Autodesk Fusion 360 part; units mm, degrees
(part 5 of 6)
equation "lip_t = 3 mm" comment "SOURCE: Control's allocation of 611408 (#279): a 3 mm aluminium lip angle, as the casing"
equation "lip_h = 40 mm" comment "ASSUMPTION: the lip's upright leg on the box's front wall, room for its 3 rivets 20 above the foot leg and below the bulkhead (Z 1698)"
equation "lip_tip = 2 mm" comment "CALCULATION: the lip's tip stays this far off DR's skin (the PM's 25 mm reach less 2)"
equation "lip_end = 5 mm" comment "CALCULATION: the lip's right end this far short of F02 (X 1025.85)"
equation "pad_l = 40 mm" comment "SOURCE: Control's allocation of 618402 (#279): rubber pad 40 x 15 x 5"
equation "pad_w = 15 mm" comment "SOURCE: Control's allocation of 618402 (#279): rubber pad 40 x 15 x 5"
equation "pad_t = 5 mm" comment "SOURCE: Control's allocation of 618402 (#279): rubber pad 40 x 15 x 5"
equation "pad_in = 5 mm" comment "CALCULATION: each pad this far in from the lip's ends: the left at X 678, the right at X 980.85, on F08's free end past the box, since the riser puts the weight centre near the box's right end (about X 940)"
equation "buf_d = 20 mm" comment "ASSUMPTION: the riser buffer's rubber body, about 20 across (product HOLD)"
equation "buf_gap = 0 mm" comment "CALCULATION: the buffer is set to touch F07: about 15 N of the assembly's lean (CEILING, 2026-11-01) holds the riser's foot back with DR's inner panel off"
equation "dr_fac_xa = 1049.7 mm" comment "SOURCE: FRONT's DR STEP on #313 (541fe7f, 350003 P01, every tube 3 off its skin): C04's inner face, front end, X"
equation "dr_fac_ya = -817.11 mm" comment "SOURCE: FRONT's DR STEP on #313 (541fe7f, 350003 P01, every tube 3 off its skin): C04's inner face, front end, Y"
equation "dr_fac_xb = 1217.23 mm" comment "SOURCE: FRONT's DR STEP on #313 (541fe7f, 350003 P01, every tube 3 off its skin): C04's inner face, back end, X"
equation "dr_fac_yb = -666.5 mm" comment "SOURCE: FRONT's DR STEP on #313 (541fe7f, 350003 P01, every tube 3 off its skin): C04's inner face, back end, Y"
equation "ut_clr = 3 mm" comment "ASSUMPTION: the transition keeps this far off C04, so no metal touches DR's frame"
equation "air_sk_ref = 4000 mm" comment "ASSUMPTION: the polygon sketches' reference point sits this far off the origin on both axes, so each corner's dimension stays positive whatever the pod's size (FRONT's sk_ref pattern)"
equation "fac_len = sqrt(( dr_fac_xb - dr_fac_xa ) * ( dr_fac_xb - dr_fac_xa ) + ( dr_fac_yb - dr_fac_ya ) * ( dr_fac_yb - dr_fac_ya ))" comment "CALCULATION: C04's inner face, its length in plan"
equation "ut_ax = dr_fac_xa - ut_clr * ( dr_fac_yb - dr_fac_ya ) / fac_len" comment "CALCULATION: the transition's facet side: C04's inner face moved ut_clr into DR, a point on it, X"
equation "ut_ay = dr_fac_ya + ut_clr * ( dr_fac_xb - dr_fac_xa ) / fac_len" comment "CALCULATION: the same point, Y"
equation "ut_xf = ut_ax + ( -pod_d / 2 + sb_yf - ut_ay ) * ( dr_fac_xb - dr_fac_xa ) / ( dr_fac_yb - dr_fac_ya )" comment "CALCULATION: the transition's facet side meets its front (the box's front line), X (about 1044)"
equation "ut_yr = ut_ay + ( op_x0 + op_w - ut_ax ) * ( dr_fac_yb - dr_fac_ya ) / ( dr_fac_xb - dr_fac_xa )" comment "CALCULATION: the transition's facet side meets its right end (the opening's, X 1161), Y (about -717)"
equation "slv_t = 1 mm" comment "ASSUMPTION: roof sleeve wall, galvanised steel"
equation "rg_t = 2 mm" comment "ASSUMPTION: roof grille plate; 50 % free or more (report 7e), pattern HOLD"
equation "slv_rn_e = 20.0 mm" comment "CALCULATION: rivnut centre to any free edge: 2 x the Ø10.00 hole (D-163; HOLD-04's rule; was 19.2 for the Ø9.53), as the ceiling's"
equation "slv_rn_in = 20 mm" comment "ASSUMPTION: the rivnuts this far in from the slot's corners along their sides"
equation "slv_bulge = 14 mm" comment "ASSUMPTION: a set rivnut's blind-side bulge, about 14 across (the hole FRONT clears for body and bulge, DR model fr_hole_jf; Sherex gives no size)"
equation "slv_rn_clr = 1 mm" comment "ASSUMPTION: the bulge's clearance to cross member 1's back face"
equation "slv_fl_l = 40 mm" comment "CALCULATION: the flange on the slot's left side: its rivnuts slv_rn_e in, slv_rn_e to its edge, rounded up"
equation "slv_fl_f = 15 mm" comment "ASSUMPTION: the flange on the front and right sides: no rivnuts there"
equation "slv_rn_yb = ( pod_d / 2 - wall_depth ) + cs_front - x1_ov + tube_w + slv_bulge / 2 + slv_rn_clr" comment "CALCULATION: the back side's rivnuts behind cross member 1: its back face plus half the bulge plus the clearance (Y -273)"
equation "slv_fl_b = slv_rn_yb + slv_rn_e - ( slot_y0 + slot_d )" comment "CALCULATION: the flange on the slot's back side, out to slv_rn_e behind those rivnuts (about 72)"
equation "d9771 = floor_top"
equation "d9773 = ( ( pod_w / 2 - stack_t - col_gap ) ) - ( col_x0 )"
equation "d9774 = ( ( ( pod_d / 2 - wall_depth ) + col_d ) ) - ( dr_acc_face_y )"
equation "d9775 = abs(col_x0)"
equation "d9776 = abs(dr_acc_face_y)"
equation "d9777 = ( ( floor_top + foot_t ) ) - ( floor_top )"
equation "d9779 = ( floor_top + foot_t ) + grille_z + grille_h"
equation "d9781 = ( ( pod_w / 2 - stack_t - col_gap ) ) - ( col_x0 )"
equation "d9782 = ( ( ( pod_d / 2 - wall_depth ) + col_d ) ) - ( ( ( pod_d / 2 - wall_depth ) + col_d ) - face_t )"
equation "d9783 = abs(col_x0)"
equation "d9784 = abs(( ( pod_d / 2 - wall_depth ) + col_d ) - face_t)"
equation "d9785 = ( dt_zb ) - ( ( floor_top + foot_t ) + grille_z + grille_h )"
equation "d9787 = hub_z - hub_w / 2"
equation "d9789 = ( ( col_x0 + face_t + ang_f + ( pod_w / 2 - stack_t - col_gap ) - ang_f ) / 2 + hub_w / 2 ) - ( ( col_x0 + face_t + ang_f + ( pod_w / 2 - stack_t - col_gap ) - ang_f ) / 2 - hub_w / 2 )"
equation "d9790 = ( ( ( pod_d / 2 - wall_depth ) + col_d ) ) - ( ( ( pod_d / 2 - wall_depth ) + col_d ) - face_t - 40 mm )"
equation "d9791 = abs(( col_x0 + face_t + ang_f + ( pod_w / 2 - stack_t - col_gap ) - ang_f ) / 2 - hub_w / 2)"
equation "d9792 = abs(( ( pod_d / 2 - wall_depth ) + col_d ) - face_t - 40 mm)"
equation "d9793 = ( hub_z + hub_w / 2 ) - ( hub_z - hub_w / 2 )"
equation "d9795 = ( floor_top + foot_t ) + grille_z + grille_h"
equation "d9797 = ( col_x0 + face_t ) - ( col_x0 )"
equation "d9798 = ( ( ( pod_d / 2 - wall_depth ) + col_d ) - face_t ) - ( dr_acc_face_y )"
equation "d9799 = abs(col_x0)"
equation "d9800 = abs(dr_acc_face_y)"
equation "d9801 = ( dt_zb ) - ( ( floor_top + foot_t ) + grille_z + grille_h )"
equation "d9803 = ( floor_top + foot_t )"
equation "d9805 = ( ( pod_w / 2 - stack_t - col_gap ) ) - ( ( pod_w / 2 - stack_t - col_gap ) - plate_t )"
equation "d9806 = ( ( ( pod_d / 2 - wall_depth ) + col_d ) - face_t - ang_w ) - ( dr_acc_face_y )"
equation "d9807 = abs(( pod_w / 2 - stack_t - col_gap ) - plate_t)"
equation "d9808 = abs(dr_acc_face_y)"
equation "d9809 = ( b01_z + fr_wsh_d / 2 + cart_b01_clr ) - ( ( floor_top + foot_t ) )"
equation "d9811 = b01_z + fr_wsh_d / 2 + cart_b01_clr + cart_l"
equation "d9813 = ( ( pod_w / 2 - stack_t - col_gap ) ) - ( ( pod_w / 2 - stack_t - col_gap ) - plate_t )"
equation "d9814 = ( ( ( pod_d / 2 - wall_depth ) + col_d ) - face_t - ang_w ) - ( dr_acc_face_y )"
equation "d9815 = abs(( pod_w / 2 - stack_t - col_gap ) - plate_t)"
equation "d9816 = abs(dr_acc_face_y)"
equation "d9817 = ( dt_zb ) - ( b01_z + fr_wsh_d / 2 + cart_b01_clr + cart_l )"
equation "d9819 = b01_z + fr_wsh_d / 2 + cart_b01_clr"
equation "d9821 = ( ( pod_w / 2 - stack_t - col_gap ) - ang_f ) - ( col_x0 + face_t + ang_f )"
equation "d9822 = ( ( ( pod_d / 2 - wall_depth ) + col_d ) - face_t ) - ( dr_acc_face_y + clr + cart_d )"
equation "d9823 = abs(col_x0 + face_t + ang_f)"
equation "d9824 = abs(dr_acc_face_y + clr + cart_d)"
equation "d9825 = ( b01_z + fr_wsh_d / 2 + cart_b01_clr + cart_l ) - ( b01_z + fr_wsh_d / 2 + cart_b01_clr )"
equation "d9827 = hub_z - hub_w / 2"
equation "d9829 = ( ( col_x0 + face_t + ang_f + ( pod_w / 2 - stack_t - col_gap ) - ang_f ) / 2 + hub_w / 2 ) - ( ( col_x0 + face_t + ang_f + ( pod_w / 2 - stack_t - col_gap ) - ang_f ) / 2 - hub_w / 2 )"
equation "d9830 = ( ( ( pod_d / 2 - wall_depth ) + col_d ) ) - ( ( ( pod_d / 2 - wall_depth ) + col_d ) - face_t - 40 mm )"
equation "d9831 = abs(( col_x0 + face_t + ang_f + ( pod_w / 2 - stack_t - col_gap ) - ang_f ) / 2 - hub_w / 2)"
equation "d9832 = abs(( ( pod_d / 2 - wall_depth ) + col_d ) - face_t - 40 mm)"
equation "d9833 = ( hub_z + hub_w / 2 ) - ( hub_z - hub_w / 2 )"
equation "d9835 = b01_z + fr_wsh_d / 2 + cart_b01_clr"
equation "d9837 = ( ( pod_w / 2 - stack_t - col_gap ) - cart_w ) - ( col_x0 + face_t )"
equation "d9838 = ( dr_acc_face_y + clr + cart_d ) - ( dr_acc_face_y + ang_w )"
equation "d9839 = abs(col_x0 + face_t)"
equation "d9840 = abs(dr_acc_face_y + ang_w)"
equation "d9841 = ( b01_z + fr_wsh_d / 2 + cart_b01_clr + cart_l ) - ( b01_z + fr_wsh_d / 2 + cart_b01_clr )"
equation "d9843 = ( floor_top + foot_t ) + grille_z"
equation "d9845 = ( ( pod_w / 2 - stack_t - col_gap ) ) - ( col_x0 )"
equation "d9846 = ( ( ( pod_d / 2 - wall_depth ) + col_d ) ) - ( ( ( pod_d / 2 - wall_depth ) + col_d ) - grille_t )"
equation "d9847 = abs(col_x0)"
equation "d9848 = abs(( ( pod_d / 2 - wall_depth ) + col_d ) - grille_t)"
equation "d9849 = ( ( floor_top + foot_t ) + grille_z + grille_h ) - ( ( floor_top + foot_t ) + grille_z )"
equation "d9851 = ( floor_top + foot_t ) + grille_z"
equation "d9853 = ( col_x0 + grille_t ) - ( col_x0 )"
equation "d9854 = ( ( ( pod_d / 2 - wall_depth ) + col_d ) - grille_t ) - ( ( ( pod_d / 2 - wall_depth ) + col_d ) - grille_t - grille_l )"
equation "d9855 = abs(col_x0)"
equation "d9856 = abs(( ( pod_d / 2 - wall_depth ) + col_d ) - grille_t - grille_l)"
equation "d9857 = ( ( floor_top + foot_t ) + grille_z + grille_h ) - ( ( floor_top + foot_t ) + grille_z )"
equation "d9859 = hub_z - hub_w / 2"
equation "d9861 = ( ( col_x0 + face_t + ang_f + ( pod_w / 2 - stack_t - col_gap ) - ang_f ) / 2 + hub_w / 2 ) - ( ( col_x0 + face_t + ang_f + ( pod_w / 2 - stack_t - col_gap ) - ang_f ) / 2 - hub_w / 2 )"
equation "d9862 = ( ( ( pod_d / 2 - wall_depth ) + col_d ) ) - ( ( ( pod_d / 2 - wall_depth ) + col_d ) - hub_t )"
equation "d9863 = abs(( col_x0 + face_t + ang_f + ( pod_w / 2 - stack_t - col_gap ) - ang_f ) / 2 - hub_w / 2)"
equation "d9864 = abs(( ( pod_d / 2 - wall_depth ) + col_d ) - hub_t)"
equation "d9865 = ( hub_z + hub_w / 2 ) - ( hub_z - hub_w / 2 )"
equation "d9867 = abs(( col_x0 + face_t ) - ( col_x0 + face_t ))"
equation "d9868 = abs(( ( ( pod_d / 2 - wall_depth ) + col_d ) - face_t - ang_w + ang_w ) - ( ( ( pod_d / 2 - wall_depth ) + col_d ) - face_t - ang_w ))"
equation "d9869 = abs(( col_x0 + face_t + ang_f ) - ( col_x0 + face_t ))"
equation "d9870 = abs(( ( ( pod_d / 2 - wall_depth ) + col_d ) - face_t - ang_w + ang_w - ang_t ) - ( ( ( pod_d / 2 - wall_depth ) + col_d ) - face_t - ang_w ))"
equation "d9871 = abs(( col_x0 + face_t + ang_t ) - ( col_x0 + face_t ))"
equation "d9872 = abs(( ( ( pod_d / 2 - wall_depth ) + col_d ) - face_t - ang_w ) - ( ( ( pod_d / 2 - wall_depth ) + col_d ) - face_t - ang_w ))"
equation "d9873 = ( ( dt_zb ) - ( ( floor_top + foot_t ) ) ) - ( 0 mm )"
equation "d9875 = ( floor_top + foot_t )"
equation "d9877 = abs(col_x0 + face_t)"
equation "d9878 = abs(( ( pod_d / 2 - wall_depth ) + col_d ) - face_t - ang_w)"
equation "d9883 = dt_zb"
equation "d9885 = abs(( pod_w / 2 - stack_t - col_gap ) - ang_f + ang_f)"
equation "d9886 = abs(( ( pod_d / 2 - wall_depth ) + col_d ) - face_t - ang_w)"
equation "d9891 = ( floor_top + foot_t )"
equation "d9893 = abs(col_x0 + face_t)"
equation "d9894 = abs(dr_acc_face_y)"
equation "d9895 = abs(col_x0 + face_t + ang_w)"
equation "d9896 = abs(dr_acc_face_y + ang_t)"
equation "d9897 = abs(col_x0 + face_t + ang_t)"
equation "d9898 = abs(dr_acc_face_y + ang_w)"
equation "d9899 = ( dt_zb ) - ( ( floor_top + foot_t ) )"
equation "d9901 = b01_z + fr_wsh_d / 2 + cart_b01_clr"
equation "d9903 = ( ( pod_w / 2 - stack_t - col_gap ) ) - ( ( pod_w / 2 - stack_t - col_gap ) - cart_w )"
equation "d9904 = ( dr_acc_face_y + clr + cart_d ) - ( dr_acc_face_y + clr )"
equation "d9905 = abs(( pod_w / 2 - stack_t - col_gap ) - cart_w)"
equation "d9906 = abs(dr_acc_face_y + clr)"
equation "d9907 = ( b01_z + fr_wsh_d / 2 + cart_b01_clr + cart_l ) - ( b01_z + fr_wsh_d / 2 + cart_b01_clr )"
equation "d9909 = cart_t"
equation "d9910 = ( ( ( pod_w / 2 - stack_t - col_gap ) - cart_t ) - ( ( pod_w / 2 - stack_t - col_gap ) - cart_w + cart_t ) ) - ( 0 mm )"
equation "d9911 = ( ( dr_acc_face_y + clr + cart_t + 0 * ( lay_t + pass_w ) + lay_t ) - ( dr_acc_face_y + clr + cart_t + 0 * ( lay_t + pass_w ) ) ) - ( 0 mm )"
equation "d9912 = ( ( b01_z + fr_wsh_d / 2 + cart_b01_clr + cart_l ) - ( b01_z + fr_wsh_d / 2 + cart_b01_clr ) ) - ( 0 mm )"
equation "d9914 = b01_z + fr_wsh_d / 2 + cart_b01_clr"
equation "d9916 = abs(( pod_w / 2 - stack_t - col_gap ) - cart_w + cart_t)"
equation "d9917 = abs(dr_acc_face_y + clr + cart_t + 0 * ( lay_t + pass_w ))"
equation "d9922 = b01_z + fr_wsh_d / 2 + cart_b01_clr"
equation "d9924 = abs(( pod_w / 2 - stack_t - col_gap ) - cart_w + cart_t)"
equation "d9925 = abs(dr_acc_face_y + clr + cart_t + 1 * ( lay_t + pass_w ))"
equation "d9930 = b01_z + fr_wsh_d / 2 + cart_b01_clr"
equation "d9932 = abs(( pod_w / 2 - stack_t - col_gap ) - cart_w + cart_t)"
equation "d9933 = abs(dr_acc_face_y + clr + cart_t + 2 * ( lay_t + pass_w ))"
equation "d9938 = dt_zb"
equation "d9940 = ( -us_gap / 2 ) - ( ( -pod_w / 2 + stack_t + col_gap ) )"
equation "d9941 = ( ( ( pod_d / 2 - wall_depth ) + col_d ) - face_t ) - ( dr_acc_face_y )"
equation "d9942 = abs(( -pod_w / 2 + stack_t + col_gap ))"
equation "d9943 = abs(dr_acc_face_y)"
equation "d9944 = ( dt_zb + face_t ) - ( dt_zb )"
equation "d9946 = dt_zb"
equation "d9948 = ( ( -pod_w / 2 + stack_t ) + eg_x0 + eg_l ) - ( ( -pod_w / 2 + stack_t ) + eg_x0 )"
equation "d9949 = ( ( pod_d / 2 - wall_depth ) + face_t + eg_w ) - ( ( pod_d / 2 - wall_depth ) + face_t )"
equation "d9950 = abs(( -pod_w / 2 + stack_t ) + eg_x0)"
equation "d9951 = abs(( pod_d / 2 - wall_depth ) + face_t)"
equation "d9952 = ( dt_zb + face_t ) - ( dt_zb )"
equation "d9954 = dt_zb"
equation "d9956 = ( col_x0 - us_gap / 2 ) - ( us_gap / 2 )"
equation "d9957 = ( ( ( pod_d / 2 - wall_depth ) + col_d ) - face_t ) - ( dr_acc_face_y )"
equation "d9958 = abs(us_gap / 2)"
equation "d9959 = abs(dr_acc_face_y)"
equation "d9960 = ( dt_zb + face_t ) - ( dt_zb )"
equation "d9962 = dt_zb"
equation "d9964 = ( ( pod_w / 2 - stack_t - col_gap ) ) - ( col_x0 )"
equation "d9965 = ( ( ( pod_d / 2 - wall_depth ) + col_d ) - face_t ) - ( dr_acc_face_y )"
equation "d9966 = abs(col_x0)"
equation "d9967 = abs(dr_acc_face_y)"
equation "d9968 = ( dt_zb + face_t ) - ( dt_zb )"
equation "d9970 = dt_zb"
equation "d9972 = ( ( pod_w / 2 - stack_t - col_gap ) ) - ( ( -pod_w / 2 + stack_t + col_gap ) )"
equation "d9973 = ( ( ( pod_d / 2 - wall_depth ) + col_d ) ) - ( ( ( pod_d / 2 - wall_depth ) + col_d ) - face_t )"
equation "d9974 = abs(( -pod_w / 2 + stack_t + col_gap ))"
equation "d9975 = abs(( ( pod_d / 2 - wall_depth ) + col_d ) - face_t)"
equation "d9976 = ( ( pod_h - outer_t - rvn_head - ( stud_l - stud_eng ) ) ) - ( dt_zb )"
equation "d9978 = ( ( pod_h - outer_t - rvn_head - ( stud_l - stud_eng ) ) - hd_h - hd_c )"
equation "d9980 = ( -hang_x + stud_d / 2 + hd_c ) - ( -hang_x - stud_d / 2 - hd_c )"
equation "d9981 = ( ( ( pod_d / 2 - wall_depth ) + col_d ) ) - ( ( ( pod_d / 2 - wall_depth ) + col_d ) - face_t )"
equation "d9982 = abs(-hang_x - stud_d / 2 - hd_c)"
equation "d9983 = abs(( ( pod_d / 2 - wall_depth ) + col_d ) - face_t)"
equation "d9984 = ( ( pod_h - outer_t - rvn_head - ( stud_l - stud_eng ) ) ) - ( ( ( pod_h - outer_t - rvn_head - ( stud_l - stud_eng ) ) - hd_h - hd_c ) )"
equation "d9986 = ( ( pod_h - outer_t - rvn_head - ( stud_l - stud_eng ) ) - hd_h - hd_c )"
equation "d9988 = ( hang_x + stud_d / 2 + hd_c ) - ( hang_x - stud_d / 2 - hd_c )"
equation "d9989 = ( ( ( pod_d / 2 - wall_depth ) + col_d ) ) - ( ( ( pod_d / 2 - wall_depth ) + col_d ) - face_t )"
equation "d9990 = abs(hang_x - stud_d / 2 - hd_c)"
equation "d9991 = abs(( ( pod_d / 2 - wall_depth ) + col_d ) - face_t)"
equation "d9992 = ( ( pod_h - outer_t - rvn_head - ( stud_l - stud_eng ) ) ) - ( ( ( pod_h - outer_t - rvn_head - ( stud_l - stud_eng ) ) - hd_h - hd_c ) )"
equation "d9994 = ( ( pod_h - outer_t - rvn_head - ( stud_l - stud_eng ) ) - hd_h - hd_c )"
equation "d9996 = ( -lock_x + stud_d / 2 + hd_c ) - ( -lock_x - stud_d / 2 - hd_c )"
equation "d9997 = ( ( ( pod_d / 2 - wall_depth ) + col_d ) ) - ( ( ( pod_d / 2 - wall_depth ) + col_d ) - face_t )"
equation "d9998 = abs(-lock_x - stud_d / 2 - hd_c)"
equation "d9999 = abs(( ( pod_d / 2 - wall_depth ) + col_d ) - face_t)"
equation "d10000 = ( ( pod_h - outer_t - rvn_head - ( stud_l - stud_eng ) ) ) - ( ( ( pod_h - outer_t - rvn_head - ( stud_l - stud_eng ) ) - hd_h - hd_c ) )"
equation "d10002 = ( ( pod_h - outer_t - rvn_head - ( stud_l - stud_eng ) ) - hd_h - hd_c )"
equation "d10004 = ( -lock_x + lock_dx + stud_d / 2 + hd_c ) - ( -lock_x + lock_dx - stud_d / 2 - hd_c )"
equation "d10005 = ( ( ( pod_d / 2 - wall_depth ) + col_d ) ) - ( ( ( pod_d / 2 - wall_depth ) + col_d ) - face_t )"
equation "d10006 = abs(-lock_x + lock_dx - stud_d / 2 - hd_c)"
equation "d10007 = abs(( ( pod_d / 2 - wall_depth ) + col_d ) - face_t)"
equation "d10008 = ( ( pod_h - outer_t - rvn_head - ( stud_l - stud_eng ) ) ) - ( ( ( pod_h - outer_t - rvn_head - ( stud_l - stud_eng ) ) - hd_h - hd_c ) )"
equation "d10010 = ( pod_h - outer_t - rvn_head - ( stud_l - stud_eng ) )"
equation "d10012 = ( ( pod_w / 2 - stack_t - col_gap ) ) - ( ( -pod_w / 2 + stack_t + col_gap ) )"
equation "d10013 = ( ( pod_d / 2 - wall_depth ) + rail_w ) - ( dr_acc_face_y )"
equation "d10014 = abs(( -pod_w / 2 + stack_t + col_gap ))"
equation "d10015 = abs(dr_acc_face_y)"
equation "d10016 = ( ( pod_h - outer_t - rvn_head - ( stud_l - stud_eng ) ) + rail_t ) - ( ( pod_h - outer_t - rvn_head - ( stud_l - stud_eng ) ) )"
equation "d10018 = ( pod_h - outer_t - rvn_head - ( stud_l - stud_eng ) )"
equation "d10020 = ( ( pod_w / 2 - stack_t - col_gap ) ) - ( ( -pod_w / 2 + stack_t + col_gap ) )"
equation "d10021 = ( ( ( pod_d / 2 - wall_depth ) + col_d ) ) - ( ( ( pod_d / 2 - wall_depth ) + col_d ) - rail_w )"
equation "d10022 = abs(( -pod_w / 2 + stack_t + col_gap ))"
equation "d10023 = abs(( ( pod_d / 2 - wall_depth ) + col_d ) - rail_w)"
equation "d10024 = ( ( pod_h - outer_t - rvn_head - ( stud_l - stud_eng ) ) + rail_t ) - ( ( pod_h - outer_t - rvn_head - ( stud_l - stud_eng ) ) )"
equation "d10026 = dt_zb + face_t + hl_h"
equation "d10028 = ( ( pod_w / 2 - stack_t - col_gap ) ) - ( ( -pod_w / 2 + stack_t + col_gap ) )"
equation "d10029 = ( dr_acc_face_y + dp_t ) - ( dr_acc_face_y )"
equation "d10030 = abs(( -pod_w / 2 + stack_t + col_gap ))"
equation "d10031 = abs(dr_acc_face_y)"
equation "d10032 = ( ( pod_h - outer_t - rvn_head - ( stud_l - stud_eng ) ) ) - ( dt_zb + face_t + hl_h )"
equation "d10034 = ( ( pod_h - outer_t - rvn_head - ( stud_l - stud_eng ) ) - hd_h - hd_c )"
equation "d10036 = ( -hang_x + stud_d / 2 + hd_c ) - ( -hang_x - stud_d / 2 - hd_c )"
equation "d10037 = ( dr_acc_face_y + dp_t ) - ( dr_acc_face_y )"
equation "d10038 = abs(-hang_x - stud_d / 2 - hd_c)"
equation "d10039 = abs(dr_acc_face_y)"
equation "d10040 = ( ( pod_h - outer_t - rvn_head - ( stud_l - stud_eng ) ) ) - ( ( ( pod_h - outer_t - rvn_head - ( stud_l - stud_eng ) ) - hd_h - hd_c ) )"
equation "d10042 = ( ( pod_h - outer_t - rvn_head - ( stud_l - stud_eng ) ) - hd_h - hd_c )"
equation "d10044 = ( hang_x + stud_d / 2 + hd_c ) - ( hang_x - stud_d / 2 - hd_c )"
equation "d10045 = ( dr_acc_face_y + dp_t ) - ( dr_acc_face_y )"
equation "d10046 = abs(hang_x - stud_d / 2 - hd_c)"
equation "d10047 = abs(dr_acc_face_y)"
equation "d10048 = ( ( pod_h - outer_t - rvn_head - ( stud_l - stud_eng ) ) ) - ( ( ( pod_h - outer_t - rvn_head - ( stud_l - stud_eng ) ) - hd_h - hd_c ) )"
equation "d10050 = dt_zb + face_t"
equation "d10052 = ( ( -pod_w / 2 + stack_t + col_gap ) + box_t ) - ( ( -pod_w / 2 + stack_t + col_gap ) )"
equation "d10053 = ( ( ( pod_d / 2 - wall_depth ) + col_d ) - face_t ) - ( dr_acc_face_y + dp_t )"
equation "d10054 = abs(( -pod_w / 2 + stack_t + col_gap ))"
equation "d10055 = abs(dr_acc_face_y + dp_t)"
equation "d10056 = ( ( ( pod_h - outer_t - rvn_head - ( stud_l - stud_eng ) ) - hd_h - hd_c ) ) - ( dt_zb + face_t )"
equation "d10058 = dt_zb + face_t"
equation "d10060 = ( ( pod_w / 2 - stack_t - col_gap ) ) - ( ( pod_w / 2 - stack_t - col_gap ) - fb_w - cart_l )"
equation "d10061 = ( ( ( pod_d / 2 - wall_depth ) + col_d ) - face_t - hl_h ) - ( dr_acc_face_y + clr )"
equation "d10062 = abs(( pod_w / 2 - stack_t - col_gap ) - fb_w - cart_l)"
equation "d10063 = abs(dr_acc_face_y + clr)"
equation "d10064 = ( dt_zb + face_t + sof_fill_t ) - ( dt_zb + face_t )"
equation "d10066 = b08_z - fr_hd_d / 2 - fr_scr_clr"
equation "d10068 = ( b08_x1 + fr_hd_d / 2 + fr_scr_clr ) - ( b08_x1 - fr_hd_d / 2 - fr_scr_clr )"
equation "d10069 = ( dr_acc_face_y + fr_wsh_t + fr_hd_h + fr_scr_clr ) - ( dr_acc_face_y + clr )"
equation "d10070 = abs(b08_x1 - fr_hd_d / 2 - fr_scr_clr)"
equation "d10071 = abs(dr_acc_face_y + clr)"
equation "d10072 = ( b08_z + fr_hd_d / 2 + fr_scr_clr ) - ( b08_z - fr_hd_d / 2 - fr_scr_clr )"
equation "d10074 = b08_z - fr_hd_d / 2 - fr_scr_clr"
equation "d10076 = ( b08_x2 + fr_hd_d / 2 + fr_scr_clr ) - ( b08_x2 - fr_hd_d / 2 - fr_scr_clr )"
equation "d10077 = ( dr_acc_face_y + fr_wsh_t + fr_hd_h + fr_scr_clr ) - ( dr_acc_face_y + clr )"
equation "d10078 = abs(b08_x2 - fr_hd_d / 2 - fr_scr_clr)"
equation "d10079 = abs(dr_acc_face_y + clr)"
equation "d10080 = ( b08_z + fr_hd_d / 2 + fr_scr_clr ) - ( b08_z - fr_hd_d / 2 - fr_scr_clr )"
equation "d10082 = b08_z - fr_hd_d / 2 - fr_scr_clr"
equation "d10084 = ( b08_x3 + fr_hd_d / 2 + fr_scr_clr ) - ( b08_x3 - fr_hd_d / 2 - fr_scr_clr )"
equation "d10085 = ( dr_acc_face_y + fr_wsh_t + fr_hd_h + fr_scr_clr ) - ( dr_acc_face_y + clr )"
equation "d10086 = abs(b08_x3 - fr_hd_d / 2 - fr_scr_clr)"
equation "d10087 = abs(dr_acc_face_y + clr)"
equation "d10088 = ( b08_z + fr_hd_d / 2 + fr_scr_clr ) - ( b08_z - fr_hd_d / 2 - fr_scr_clr )"
equation "d10090 = dt_zb + face_t + sof_fill_t"
equation "d10092 = ( ( pod_w / 2 - stack_t - col_gap ) ) - ( ( pod_w / 2 - stack_t - col_gap ) - fb_w - cart_l )"
equation "d10093 = ( ( ( pod_d / 2 - wall_depth ) + col_d ) - face_t ) - ( dr_acc_face_y + clr + cart_d )"
equation "d10094 = abs(( pod_w / 2 - stack_t - col_gap ) - fb_w - cart_l)"
equation "d10095 = abs(dr_acc_face_y + clr + cart_d)"
equation "d10096 = ( ( ( pod_h - outer_t - rvn_head - ( stud_l - stud_eng ) ) - hd_h - hd_c ) ) - ( dt_zb + face_t + sof_fill_t )"
equation "d10098 = dt_zb"
equation "d10100 = ( ( -pod_w / 2 + stack_t ) + eg_x0 + eg_l ) - ( ( -pod_w / 2 + stack_t ) + eg_x0 )"
equation "d10101 = ( ( pod_d / 2 - wall_depth ) + face_t + eg_w ) - ( ( pod_d / 2 - wall_depth ) + face_t )"
equation "d10102 = abs(( -pod_w / 2 + stack_t ) + eg_x0)"
equation "d10103 = abs(( pod_d / 2 - wall_depth ) + face_t)"
equation "d10104 = ( dt_zb + grille_t ) - ( dt_zb )"
equation "d10106 = ( stud_d ) - ( 0 mm )"
equation "d10107 = ( stud_d ) - ( 0 mm )"
equation "d10108 = ( hd_h ) - ( 0 mm )"
equation "d10110 = hd_h"
equation "d10113 = abs(stud_d / 2)"
equation "d10114 = abs(stud_d / 2)"
equation "d10115 = ( ( ( pod_h - outer_t - rvn_head ) ) - ( ( pod_h - outer_t - rvn_head - ( stud_l - stud_eng ) ) - hd_h ) ) - ( hd_h )"
equation "d10117 = ( pod_h - outer_t - rvn_head - ( stud_l - stud_eng ) ) - hd_h"
equation "d10119 = abs(-hang_x - stud_d / 2)"
equation "d10120 = abs(( pod_d / 2 - wall_depth ) + tube_w / 2 - stud_d / 2)"
equation "d10125 = ( pod_h - outer_t - rvn_head - ( stud_l - stud_eng ) ) - hd_h"
equation "d10127 = abs(-hang_x - stud_d / 2)"
equation "d10128 = abs(( pod_d / 2 - wall_depth ) + cs_front - x1_ov + tube_w / 2 - stud_d / 2)"
equation "d10133 = ( pod_h - outer_t - rvn_head - ( stud_l - stud_eng ) ) - hd_h"
equation "d10135 = abs(hang_x - stud_d / 2)"
equation "d10136 = abs(( pod_d / 2 - wall_depth ) + tube_w / 2 - stud_d / 2)"
equation "d10141 = ( pod_h - outer_t - rvn_head - ( stud_l - stud_eng ) ) - hd_h"
equation "d10143 = abs(hang_x - stud_d / 2)"
equation "d10144 = abs(( pod_d / 2 - wall_depth ) + cs_front - x1_ov + tube_w / 2 - stud_d / 2)"
equation "d10149 = ( ( ( ( -pod_w / 2 + stack_t + col_gap ) ) + ( ( -us_gap / 2 ) - ( ( -pod_w / 2 + stack_t + col_gap ) ) ) * 1 / 4 + hinge_l / 2 ) - ( ( ( -pod_w / 2 + stack_t + col_gap ) ) + ( ( -us_gap / 2 ) - ( ( -pod_w / 2 + stack_t + col_gap ) ) ) * 1 / 4 - hinge_l / 2 ) ) - ( 0 mm )"
equation "d10150 = ( ( dr_acc_face_y + clr ) - ( dr_acc_face_y ) ) - ( 0 mm )"
equation "d10151 = ( ( dt_zb + face_t + hl_h ) - ( dt_zb + face_t ) ) - ( 0 mm )"
equation "d10153 = dt_zb + face_t"
equation "d10155 = abs(( ( -pod_w / 2 + stack_t + col_gap ) ) + ( ( -us_gap / 2 ) - ( ( -pod_w / 2 + stack_t + col_gap ) ) ) * 1 / 4 - hinge_l / 2)"
equation "d10156 = abs(dr_acc_face_y)"
equation "d10161 = dt_zb + face_t"
equation "d10163 = abs(( ( -pod_w / 2 + stack_t + col_gap ) ) + ( ( -us_gap / 2 ) - ( ( -pod_w / 2 + stack_t + col_gap ) ) ) * 3 / 4 - hinge_l / 2)"
equation "d10164 = abs(dr_acc_face_y)"
equation "d10169 = dt_zb + face_t"
equation "d10171 = abs(( us_gap / 2 ) + ( ( col_x0 - us_gap / 2 ) - ( us_gap / 2 ) ) * 1 / 4 - hinge_l / 2)"
equation "d10172 = abs(dr_acc_face_y)"
equation "d10177 = dt_zb + face_t"
equation "d10179 = abs(( us_gap / 2 ) + ( ( col_x0 - us_gap / 2 ) - ( us_gap / 2 ) ) * 3 / 4 - hinge_l / 2)"
equation "d10180 = abs(dr_acc_face_y)"
equation "d10185 = ( ( ( ( -pod_w / 2 + stack_t + col_gap ) ) + ( ( -us_gap / 2 ) - ( ( -pod_w / 2 + stack_t + col_gap ) ) ) * 1 / 4 + latch_l / 2 ) - ( ( ( -pod_w / 2 + stack_t + col_gap ) ) + ( ( -us_gap / 2 ) - ( ( -pod_w / 2 + stack_t + col_gap ) ) ) * 1 / 4 - latch_l / 2 ) ) - ( 0 mm )"
equation "d10186 = ( ( ( ( pod_d / 2 - wall_depth ) + col_d ) - face_t ) - ( ( ( pod_d / 2 - wall_depth ) + col_d ) - face_t - hl_h ) ) - ( 0 mm )"
equation "d10187 = ( ( dt_zb + face_t + hl_h ) - ( dt_zb + face_t ) ) - ( 0 mm )"
equation "d10189 = dt_zb + face_t"
equation "d10191 = abs(( ( -pod_w / 2 + stack_t + col_gap ) ) + ( ( -us_gap / 2 ) - ( ( -pod_w / 2 + stack_t + col_gap ) ) ) * 1 / 4 - latch_l / 2)"
equation "d10192 = abs(( ( pod_d / 2 - wall_depth ) + col_d ) - face_t - hl_h)"
equation "d10197 = dt_zb + face_t"
equation "d10199 = abs(( ( -pod_w / 2 + stack_t + col_gap ) ) + ( ( -us_gap / 2 ) - ( ( -pod_w / 2 + stack_t + col_gap ) ) ) * 3 / 4 - latch_l / 2)"
equation "d10200 = abs(( ( pod_d / 2 - wall_depth ) + col_d ) - face_t - hl_h)"
equation "d10205 = dt_zb + face_t"
equation "d10207 = abs(( us_gap / 2 ) + ( ( col_x0 - us_gap / 2 ) - ( us_gap / 2 ) ) * 1 / 4 - latch_l / 2)"
equation "d10208 = abs(( ( pod_d / 2 - wall_depth ) + col_d ) - face_t - hl_h)"
equation "d10213 = dt_zb + face_t"
equation "d10215 = abs(( us_gap / 2 ) + ( ( col_x0 - us_gap / 2 ) - ( us_gap / 2 ) ) * 3 / 4 - latch_l / 2)"
equation "d10216 = abs(( ( pod_d / 2 - wall_depth ) + col_d ) - face_t - hl_h)"
equation "d10221 = ( stud_d ) - ( 0 mm )"
equation "d10222 = ( stud_d ) - ( 0 mm )"
equation "d10223 = ( hd_h ) - ( 0 mm )"
equation "d10225 = hd_h"
equation "d10228 = abs(stud_d / 2)"
equation "d10229 = abs(stud_d / 2)"
equation "d10230 = ( ( ( pod_h - outer_t - rvn_head ) ) - ( ( pod_h - outer_t - rvn_head - ( stud_l - stud_eng ) ) - hd_h ) ) - ( hd_h )"
equation "d10232 = ( pod_h - outer_t - rvn_head - ( stud_l - stud_eng ) ) - hd_h"
equation "d10234 = abs(-lock_x - stud_d / 2)"
equation "d10235 = abs(( pod_d / 2 - wall_depth ) + cs_front - x1_ov + tube_w / 2 - stud_d / 2)"
equation "d10240 = ( pod_h - outer_t - rvn_head - ( stud_l - stud_eng ) ) - hd_h"
equation "d10242 = abs(-lock_x + lock_dx - stud_d / 2)"
equation "d10243 = abs(( pod_d / 2 - wall_depth ) + cs_front - x1_ov + tube_w / 2 - stud_d / 2)"
equation "d10248 = dt_zb + face_t + sof_fill_t"
equation "d10250 = ( ( pod_w / 2 - stack_t - col_gap ) - fb_w ) - ( ( pod_w / 2 - stack_t - col_gap ) - fb_w - cart_l )"
equation "d10251 = ( dr_acc_face_y + clr + cart_d ) - ( dr_acc_face_y + clr )"
equation "d10252 = abs(( pod_w / 2 - stack_t - col_gap ) - fb_w - cart_l)"
equation "d10253 = abs(dr_acc_face_y + clr)"
equation "d10254 = ( dt_zb + face_t + sof_fill_t + cart_w ) - ( dt_zb + face_t + sof_fill_t )"
equation "d10256 = cart_t"
equation "d10257 = ( ( ( pod_w / 2 - stack_t - col_gap ) - fb_w ) - ( ( pod_w / 2 - stack_t - col_gap ) - fb_w - cart_l ) ) - ( 0 mm )"
equation "d10258 = ( ( dr_acc_face_y + clr + cart_t + 0 * ( lay_t + pass_w ) + lay_t ) - ( dr_acc_face_y + clr + cart_t + 0 * ( lay_t + pass_w ) ) ) - ( 0 mm )"
equation "d10259 = ( ( dt_zb + face_t + sof_fill_t + cart_w - cart_t ) - ( dt_zb + face_t + sof_fill_t + cart_t ) ) - ( 0 mm )"
equation "d10261 = dt_zb + face_t + sof_fill_t + cart_t"
equation "d10263 = abs(( pod_w / 2 - stack_t - col_gap ) - fb_w - cart_l)"
equation "d10264 = abs(dr_acc_face_y + clr + cart_t + 0 * ( lay_t + pass_w ))"
equation "d10269 = dt_zb + face_t + sof_fill_t + cart_t"
equation "d10271 = abs(( pod_w / 2 - stack_t - col_gap ) - fb_w - cart_l)"
equation "d10272 = abs(dr_acc_face_y + clr + cart_t + 1 * ( lay_t + pass_w ))"
equation "d10277 = dt_zb + face_t + sof_fill_t + cart_t"
equation "d10279 = abs(( pod_w / 2 - stack_t - col_gap ) - fb_w - cart_l)"
equation "d10280 = abs(dr_acc_face_y + clr + cart_t + 2 * ( lay_t + pass_w ))"
equation "d10285 = dt_zb + face_t + sof_fill_t"
equation "d10287 = ( ( pod_w / 2 - stack_t - col_gap ) ) - ( ( pod_w / 2 - stack_t - col_gap ) - fb_w )"
equation "d10288 = ( dr_acc_face_y + clr + cart_d ) - ( dr_acc_face_y + clr )"
equation "d10289 = abs(( pod_w / 2 - stack_t - col_gap ) - fb_w)"
equation "d10290 = abs(dr_acc_face_y + clr)"
equation "d10291 = ( dt_zb + face_t + sof_fill_t + cart_w ) - ( dt_zb + face_t + sof_fill_t )"
equation "d10293 = fbox_t"
equation "d10294 = dt_zb + face_t + sof_fill_t + cart_w - blk_t"
equation "d10296 = ( ( pod_w / 2 - stack_t - col_gap ) - fbox_t ) - ( ( pod_w / 2 - stack_t - col_gap ) - fb_w )"
equation "d10297 = ( dr_acc_face_y + clr + cart_d - fbox_t ) - ( dr_acc_face_y + clr + fbox_t )"
equation "d10298 = abs(( pod_w / 2 - stack_t - col_gap ) - fb_w)"
equation "d10299 = abs(dr_acc_face_y + clr + fbox_t)"
equation "d10300 = ( dt_zb + face_t + sof_fill_t + cart_w ) - ( dt_zb + face_t + sof_fill_t + cart_w - blk_t )"
equation "d10302 = ( ( ( pod_w / 2 - stack_t - col_gap ) - fbox_t ) - ( ( pod_w / 2 - stack_t - col_gap ) - fb_w ) ) - ( 0 mm )"
equation "d10303 = ( ( dr_acc_face_y + clr + fbox_t + lin_t ) - ( dr_acc_face_y + clr + fbox_t ) ) - ( 0 mm )"
equation "d10304 = ( ( dt_zb + face_t + sof_fill_t + cart_w - blk_t - fan_t ) - ( dt_zb + face_t + sof_fill_t + fbox_t ) ) - ( 0 mm )"
equation "d10306 = dt_zb + face_t + sof_fill_t + fbox_t"
equation "d10308 = abs(( pod_w / 2 - stack_t - col_gap ) - fb_w)"
equation "d10309 = abs(dr_acc_face_y + clr + fbox_t)"
equation "d10314 = dt_zb + face_t + sof_fill_t + fbox_t"
equation "d10316 = abs(( pod_w / 2 - stack_t - col_gap ) - fb_w)"
equation "d10317 = abs(dr_acc_face_y + clr + cart_d - fbox_t - lin_t)"
equation "d10322 = dt_zb + face_t + sof_fill_t + fbox_t"
equation "d10324 = ( ( pod_w / 2 - stack_t - col_gap ) - fbox_t ) - ( ( pod_w / 2 - stack_t - col_gap ) - fbox_t - lin_t )"
equation "d10325 = ( dr_acc_face_y + clr + cart_d - fbox_t - lin_t ) - ( dr_acc_face_y + clr + fbox_t + lin_t )"
equation "d10326 = abs(( pod_w / 2 - stack_t - col_gap ) - fbox_t - lin_t)"
equation "d10327 = abs(dr_acc_face_y + clr + fbox_t + lin_t)"
equation "d10328 = ( dt_zb + face_t + sof_fill_t + cart_w - blk_t - fan_t - e_lin_gap ) - ( dt_zb + face_t + sof_fill_t + fbox_t )"
equation "d10330 = ( fan_s / 2 ) - ( -fan_s / 2 )"
equation "d10331 = ( fan_s / 2 ) - ( -fan_s / 2 )"
equation "d10332 = abs(-fan_s / 2)"
equation "d10333 = abs(-fan_s / 2)"
equation "d10334 = ( fan_t ) - ( 0 mm )"
equation "d10336 = dt_zb + face_t + sof_fill_t + cart_w - blk_t - fan_t"
equation "d10338 = abs(( ( pod_w / 2 - stack_t - col_gap ) - fb_w ) + ( fb_w - fbox_t ) * 1 / 4)"
equation "d10339 = abs(dr_acc_face_y + clr + cart_d / 2)"
equation "d10344 = dt_zb + face_t + sof_fill_t + cart_w - blk_t - fan_t"
equation "d10346 = abs(( ( pod_w / 2 - stack_t - col_gap ) - fb_w ) + ( fb_w - fbox_t ) * 3 / 4)"
equation "d10347 = abs(dr_acc_face_y + clr + cart_d / 2)"
equation "d10352 = sb_z0"
equation "d10354 = ( sb_x0 + sb_w ) - ( sb_x0 )"
equation "d10355 = ( ( -pod_d / 2 ) + sb_yf + sb_d ) - ( ( -pod_d / 2 ) + sb_yf )"
equation "d10356 = abs(sb_x0)"
equation "d10357 = abs(( -pod_d / 2 ) + sb_yf)"
equation "d10358 = ( sb_z0 + sb_h ) - ( sb_z0 )"
equation "d10360 = fbox_t"
equation "d10361 = sb_z0 + lin_t - blk_t"
equation "d10363 = ( sb_x0 + sb_w - fbox_t ) - ( sb_x0 + fbox_t )"
equation "d10364 = ( ( -pod_d / 2 ) + sb_yf + sb_d - fbox_t ) - ( ( -pod_d / 2 ) + sb_yf + fbox_t )"
equation "d10365 = abs(sb_x0 + fbox_t)"
equation "d10366 = abs(( -pod_d / 2 ) + sb_yf + fbox_t)"
equation "d10367 = ( sb_z0 + lin_t ) - ( sb_z0 + lin_t - blk_t )"
equation "d10369 = ( ( sb_x0 + fbox_t + lin_t ) - ( sb_x0 + fbox_t ) ) - ( 0 mm )"
equation "d10370 = ( ( ( -pod_d / 2 ) + sb_yf + sb_d - fbox_t ) - ( ( -pod_d / 2 ) + sb_yf + fbox_t ) ) - ( 0 mm )"
equation "d10371 = ( ( sb_z0 + sb_h ) - ( sb_z0 + lin_t + fan_t + s_lin_gap ) ) - ( 0 mm )"
equation "d10373 = sb_z0 + lin_t + fan_t + s_lin_gap"
equation "d10375 = abs(sb_x0 + fbox_t)"
equation "d10376 = abs(( -pod_d / 2 ) + sb_yf + fbox_t)"
equation "d10381 = sb_z0 + lin_t + fan_t + s_lin_gap"
equation "d10383 = abs(sb_x0 + sb_w - fbox_t - lin_t)"
equation "d10384 = abs(( -pod_d / 2 ) + sb_yf + fbox_t)"
equation "d10389 = air_sk_ref"
equation "d10390 = air_sk_ref"
equation "d10391 = ( ( sb_z0 + pad_t ) ) + air_sk_ref"
equation "d10392 = ( ( sb_z0 + pad_t ) + lip_h ) + air_sk_ref"
equation "d10393 = ( ( sb_z0 + pad_t ) + lip_t ) + air_sk_ref"
equation "d10394 = ( ( ( -pod_d / 2 ) + sb_yf ) ) + air_sk_ref"
equation "d10395 = ( ( ( -pod_d / 2 ) + sb_yf ) - lip_t ) + air_sk_ref"
equation "d10396 = ( ( ( -pod_d / 2 ) + dr_skin_t + lip_tip ) ) + air_sk_ref"
equation "d10397 = ( sb_x0 ) * ( 1 )"
equation "d10398 = ( ( dr_f08_x1 - lip_end ) ) - ( sb_x0 )"
equation "d10400 = ( ( sb_x0 + pad_in + pad_l ) - ( sb_x0 + pad_in ) ) - ( 0 mm )"
equation "d10401 = ( ( ( ( -pod_d / 2 ) + dr_skin_t + bond_t + dr_fr_w / 2 ) + pad_w / 2 ) - ( ( ( -pod_d / 2 ) + dr_skin_t + bond_t + dr_fr_w / 2 ) - pad_w / 2 ) ) - ( 0 mm )"
equation "d10402 = ( ( sb_z0 + pad_t ) - ( sb_z0 ) ) - ( 0 mm )"
equation "d10404 = sb_z0"
equation "d10406 = abs(sb_x0 + pad_in)"
equation "d10407 = abs(( ( -pod_d / 2 ) + dr_skin_t + bond_t + dr_fr_w / 2 ) - pad_w / 2)"
equation "d10412 = sb_z0"
equation "d10414 = abs(( dr_f08_x1 - lip_end ) - pad_in - pad_l)"
equation "d10415 = abs(( ( -pod_d / 2 ) + dr_skin_t + bond_t + dr_fr_w / 2 ) - pad_w / 2)"
equation "d10420 = dr_f07_zc - buf_d / 2"
equation "d10422 = ( ( ( rs_x0 + dr_f08_x1 ) / 2 ) + buf_d / 2 ) - ( ( ( rs_x0 + dr_f08_x1 ) / 2 ) - buf_d / 2 )"
equation "d10423 = ( rs_y0 - rvn_head ) - ( ( -pod_d / 2 ) + dr_skin_t + bond_t + dr_fr_w + buf_gap )"
equation "d10424 = abs(( ( rs_x0 + dr_f08_x1 ) / 2 ) - buf_d / 2)"
equation "d10425 = abs(( -pod_d / 2 ) + dr_skin_t + bond_t + dr_fr_w + buf_gap)"
equation "d10426 = ( dr_f07_zc + buf_d / 2 ) - ( dr_f07_zc - buf_d / 2 )"
equation "d10428 = sb_z0 + lin_t"
equation "d10430 = abs(( sb_x0 + fbox_t ) + ( sb_w - 2 * fbox_t ) * 1 / 4)"
equation "d10431 = abs(( -pod_d / 2 ) + sb_yf + sb_d / 2)"
equation "d10436 = sb_z0 + lin_t"
equation "d10438 = abs(( sb_x0 + fbox_t ) + ( sb_w - 2 * fbox_t ) * 3 / 4)"
equation "d10439 = abs(( -pod_d / 2 ) + sb_yf + sb_d / 2)"
equation "d10444 = air_sk_ref"
equation "d10445 = air_sk_ref"
equation "d10446 = ( ut_xf ) + air_sk_ref"
equation "d10447 = ( ( op_x0 + op_w ) ) + air_sk_ref"
equation "d10448 = ( sb_x0 ) + air_sk_ref"
equation "d10449 = ( ( ( -pod_d / 2 ) + sb_yf ) ) + air_sk_ref"
equation "d10450 = ( ut_yr ) + air_sk_ref"
equation "d10451 = ( ( ( -pod_d / 2 ) + decor_d - dr_back_t ) ) + air_sk_ref"
equation "d10452 = ( sb_z0 + sb_h ) * ( 1 )"
equation "d10453 = ( op_z0 + op_h ) - ( sb_z0 + sb_h )"
equation "d10455 = air_sk_ref"
equation "d10456 = air_sk_ref"
equation "d10457 = ( ut_xf ) + air_sk_ref"
equation "d10458 = ( ( op_x0 + op_w ) ) + air_sk_ref"
equation "d10459 = ( sb_x0 + sb_w ) + air_sk_ref"
equation "d10460 = ( ( ( -pod_d / 2 ) + sb_yf ) ) + air_sk_ref"
equation "d10461 = ( ut_yr ) + air_sk_ref"
equation "d10462 = ( ( ( -pod_d / 2 ) + decor_d - dr_back_t ) ) + air_sk_ref"
equation "d10463 = ( op_z0 ) * ( 1 )"
equation "d10464 = ( sb_z0 + sb_h ) - ( op_z0 )"
equation "d10466 = rs_z0"
equation "d10468 = ( rs_x0 + rs_w ) - ( rs_x0 )"
equation "d10469 = ( rs_y0 + rs_d ) - ( rs_y0 )"
equation "d10470 = abs(rs_x0)"
equation "d10471 = abs(rs_y0)"
equation "d10472 = ( rs_z1 ) - ( rs_z0 )"
equation "d10474 = air_sk_ref"
equation "d10475 = air_sk_ref"
equation "d10476 = ( rs_x0 + rs_w - rs_ch ) + air_sk_ref"
equation "d10477 = ( rs_x0 + rs_w ) + air_sk_ref"
equation "d10478 = ( rs_y0 ) + air_sk_ref"
equation "d10479 = ( rs_y0 + rs_ch ) + air_sk_ref"
equation "d10480 = ( rs_z0 - 1 mm ) * ( 1 )"
equation "d10481 = ( rs_z1 + 1 mm ) - ( rs_z0 - 1 mm )"
equation "d10483 = rs_t"
equation "d10484 = air_sk_ref"
equation "d10485 = air_sk_ref"
equation "d10486 = ( rs_x0 ) + air_sk_ref"
equation "d10487 = ( rs_x0 + rs_w ) + air_sk_ref"
equation "d10488 = ( sb_x0 + sb_w ) + air_sk_ref"
equation "d10489 = ( sb_x0 ) + air_sk_ref"
equation "d10490 = ( rs_z1 ) + air_sk_ref"
equation "d10491 = ( sb_z0 ) + air_sk_ref"
equation "d10492 = ( rs_y0 ) * ( 1 )"
equation "d10493 = ( rs_y0 + rs_d ) - ( rs_y0 )"
equation "d10495 = dt_zb + face_t + sof_fill_t + cart_w"
equation "d10497 = ( slot_x0 + slot_w ) - ( slot_x0 )"
equation "d10498 = ( slot_y0 + slot_d ) - ( slot_y0 )"
equation "d10499 = abs(slot_x0)"
equation "d10500 = abs(slot_y0)"
equation "d10501 = ( pod_h ) - ( dt_zb + face_t + sof_fill_t + cart_w )"
equation "d10503 = slv_t"
equation "d10504 = pod_h"
equation "d10506 = ( slot_x0 + slot_w + slv_fl_f ) - ( slot_x0 - slv_fl_l )"
equation "d10507 = ( slot_y0 + slot_d + slv_fl_b ) - ( slot_y0 - slv_fl_f )"
equation "d10508 = abs(slot_x0 - slv_fl_l)"
equation "d10509 = abs(slot_y0 - slv_fl_f)"
equation "d10510 = ( pod_h + slv_t ) - ( pod_h )"
equation "d10512 = pod_h"
equation "d10514 = ( slot_x0 + slot_w - slv_t ) - ( slot_x0 + slv_t )"
equation "d10515 = ( slot_y0 + slot_d - slv_t ) - ( slot_y0 + slv_t )"
equation "d10516 = abs(slot_x0 + slv_t)"
equation "d10517 = abs(slot_y0 + slv_t)"
equation "d10518 = ( pod_h + slv_t ) - ( pod_h )"
equation "d10520 = pod_h + slv_t"
equation "d10522 = ( slot_x0 + slot_w + slv_fl_f ) - ( slot_x0 - slv_fl_l )"
equation "d10523 = ( slot_y0 + slot_d + slv_fl_b ) - ( slot_y0 - slv_fl_f )"
equation "d10524 = abs(slot_x0 - slv_fl_l)"
equation "d10525 = abs(slot_y0 - slv_fl_f)"
equation "d10526 = ( pod_h + slv_t + rg_t ) - ( pod_h + slv_t )"
equation "d10528 = dr_acc_face_y"
equation "d10530 = key_d"
equation "d10531 = abs(hook_x)"
equation "d10532 = abs(hook_z1 - key_drop)"
equation "d10533 = abs(( dr_acc_face_y + ang_t ) - ( dr_acc_face_y ))"
equation "d10535 = hook_z1 - key_drop"
equation "d10537 = ( hook_x + key_w / 2 ) - ( hook_x - key_w / 2 )"
equation "d10538 = ( dr_acc_face_y + ang_t ) - ( dr_acc_face_y )"
equation "d10539 = abs(hook_x - key_w / 2)"
equation "d10540 = abs(dr_acc_face_y)"
equation "d10541 = ( hook_z1 ) - ( hook_z1 - key_drop )"
equation "d10543 = dr_acc_face_y"
equation "d10545 = key_w"
equation "d10546 = abs(hook_x)"
equation "d10547 = abs(hook_z1)"
equation "d10548 = abs(( dr_acc_face_y + ang_t ) - ( dr_acc_face_y ))"
equation "d10550 = dr_acc_face_y"
equation "d10552 = key_d"
equation "d10553 = abs(hook_x)"
equation "d10554 = abs(hook_z2 - key_drop)"
equation "d10555 = abs(( dr_acc_face_y + ang_t ) - ( dr_acc_face_y ))"
equation "d10557 = hook_z2 - key_drop"
equation "d10559 = ( hook_x + key_w / 2 ) - ( hook_x - key_w / 2 )"
equation "d10560 = ( dr_acc_face_y + ang_t ) - ( dr_acc_face_y )"
equation "d10561 = abs(hook_x - key_w / 2)"
equation "d10562 = abs(dr_acc_face_y)"
equation "d10563 = ( hook_z2 ) - ( hook_z2 - key_drop )"
equation "d10565 = dr_acc_face_y"
equation "d10567 = key_w"
equation "d10568 = abs(hook_x)"
equation "d10569 = abs(hook_z2)"
equation "d10570 = abs(( dr_acc_face_y + ang_t ) - ( dr_acc_face_y ))"
equation "d10572 = floor_top"
equation "d10574 = spg_hole"
equation "d10575 = abs(spg1_x)"
equation "d10576 = abs(spg1_y)"
equation "d10577 = ( ( floor_top + foot_t ) ) - ( floor_top )"
equation "d10579 = floor_top"
equation "d10581 = ( spg2_x + spg_hole / 2 ) - ( spg2_x - spg_hole / 2 )"
equation "d10582 = ( spg2_y + ( spg_slot - spg_hole ) / 2 ) - ( spg2_y - ( spg_slot - spg_hole ) / 2 )"
equation "d10583 = abs(spg2_x - spg_hole / 2)"
equation "d10584 = abs(spg2_y - ( spg_slot - spg_hole ) / 2)"
equation "d10585 = ( ( floor_top + foot_t ) ) - ( floor_top )"
equation "d10587 = floor_top"
equation "d10589 = spg_hole"
equation "d10590 = abs(spg2_x)"
equation "d10591 = abs(spg2_y - ( spg_slot - spg_hole ) / 2)"
equation "d10592 = ( ( floor_top + foot_t ) ) - ( floor_top )"
equation "d10594 = floor_top"
equation "d10596 = spg_hole"
equation "d10597 = abs(spg2_x)"
equation "d10598 = abs(spg2_y + ( spg_slot - spg_hole ) / 2)"
equation "d10599 = ( ( floor_top + foot_t ) ) - ( floor_top )"
equation "d10601 = ( pod_h - outer_t - rvn_head - ( stud_l - stud_eng ) )"
equation "d10603 = ( -hang_x + key_w / 2 ) - ( -hang_x - key_w / 2 )"
equation "d10604 = ( ( pod_d / 2 - wall_depth ) + tube_w / 2 ) - ( dr_acc_face_y )"
equation "d10605 = abs(-hang_x - key_w / 2)"
equation "d10606 = abs(dr_acc_face_y)"
equation "d10607 = ( ( pod_h - outer_t - rvn_head - ( stud_l - stud_eng ) ) + rail_t ) - ( ( pod_h - outer_t - rvn_head - ( stud_l - stud_eng ) ) )"
equation "d10609 = ( pod_h - outer_t - rvn_head - ( stud_l - stud_eng ) )"
equation "d10611 = key_w"
equation "d10612 = abs(-hang_x)"
equation "d10613 = abs(( pod_d / 2 - wall_depth ) + tube_w / 2)"
equation "d10614 = ( ( pod_h - outer_t - rvn_head - ( stud_l - stud_eng ) ) + rail_t ) - ( ( pod_h - outer_t - rvn_head - ( stud_l - stud_eng ) ) )"
equation "d10616 = ( pod_h - outer_t - rvn_head - ( stud_l - stud_eng ) )"
equation "d10618 = ( -hang_x + key_w / 2 ) - ( -hang_x - key_w / 2 )"
equation "d10619 = ( ( pod_d / 2 - wall_depth ) + cs_front - x1_ov + tube_w / 2 ) - ( ( ( pod_d / 2 - wall_depth ) + col_d ) - rail_w )"
equation "d10620 = abs(-hang_x - key_w / 2)"
equation "d10621 = abs(( ( pod_d / 2 - wall_depth ) + col_d ) - rail_w)"
equation "d10622 = ( ( pod_h - outer_t - rvn_head - ( stud_l - stud_eng ) ) + rail_t ) - ( ( pod_h - outer_t - rvn_head - ( stud_l - stud_eng ) ) )"
equation "d10624 = ( pod_h - outer_t - rvn_head - ( stud_l - stud_eng ) )"
equation "d10626 = key_w"
equation "d10627 = abs(-hang_x)"
equation "d10628 = abs(( pod_d / 2 - wall_depth ) + cs_front - x1_ov + tube_w / 2)"
equation "d10629 = ( ( pod_h - outer_t - rvn_head - ( stud_l - stud_eng ) ) + rail_t ) - ( ( pod_h - outer_t - rvn_head - ( stud_l - stud_eng ) ) )"
equation "d10631 = ( pod_h - outer_t - rvn_head - ( stud_l - stud_eng ) )"
equation "d10633 = ( hang_x + key_w / 2 ) - ( hang_x - key_w / 2 )"
equation "d10634 = ( ( pod_d / 2 - wall_depth ) + tube_w / 2 ) - ( dr_acc_face_y )"
equation "d10635 = abs(hang_x - key_w / 2)"
equation "d10636 = abs(dr_acc_face_y)"
equation "d10637 = ( ( pod_h - outer_t - rvn_head - ( stud_l - stud_eng ) ) + rail_t ) - ( ( pod_h - outer_t - rvn_head - ( stud_l - stud_eng ) ) )"
equation "d10639 = ( pod_h - outer_t - rvn_head - ( stud_l - stud_eng ) )"
equation "d10641 = key_w"
equation "d10642 = abs(hang_x)"
equation "d10643 = abs(( pod_d / 2 - wall_depth ) + tube_w / 2)"
equation "d10644 = ( ( pod_h - outer_t - rvn_head - ( stud_l - stud_eng ) ) + rail_t ) - ( ( pod_h - outer_t - rvn_head - ( stud_l - stud_eng ) ) )"
equation "d10646 = ( pod_h - outer_t - rvn_head - ( stud_l - stud_eng ) )"
equation "d10648 = ( hang_x + key_w / 2 ) - ( hang_x - key_w / 2 )"
equation "d10649 = ( ( pod_d / 2 - wall_depth ) + cs_front - x1_ov + tube_w / 2 ) - ( ( ( pod_d / 2 - wall_depth ) + col_d ) - rail_w )"
equation "d10650 = abs(hang_x - key_w / 2)"
equation "d10651 = abs(( ( pod_d / 2 - wall_depth ) + col_d ) - rail_w)"
equation "d10652 = ( ( pod_h - outer_t - rvn_head - ( stud_l - stud_eng ) ) + rail_t ) - ( ( pod_h - outer_t - rvn_head - ( stud_l - stud_eng ) ) )"
equation "d10654 = ( pod_h - outer_t - rvn_head - ( stud_l - stud_eng ) )"
equation "d10656 = key_w"
equation "d10657 = abs(hang_x)"
equation "d10658 = abs(( pod_d / 2 - wall_depth ) + cs_front - x1_ov + tube_w / 2)"
equation "d10659 = ( ( pod_h - outer_t - rvn_head - ( stud_l - stud_eng ) ) + rail_t ) - ( ( pod_h - outer_t - rvn_head - ( stud_l - stud_eng ) ) )"
equation "d10661 = ( pod_h - outer_t - rvn_head - ( stud_l - stud_eng ) )"
equation "d10663 = lock_hole"
equation "d10664 = abs(-lock_x)"
equation "d10665 = abs(( pod_d / 2 - wall_depth ) + cs_front - x1_ov + tube_w / 2)"
equation "d10666 = ( ( pod_h - outer_t - rvn_head - ( stud_l - stud_eng ) ) + rail_t ) - ( ( pod_h - outer_t - rvn_head - ( stud_l - stud_eng ) ) )"
equation "d10668 = ( pod_h - outer_t - rvn_head - ( stud_l - stud_eng ) )"
equation "d10670 = lock_hole"
equation "d10671 = abs(-lock_x + lock_dx)"
equation "d10672 = abs(( pod_d / 2 - wall_depth ) + cs_front - x1_ov + tube_w / 2)"
equation "d10673 = ( ( pod_h - outer_t - rvn_head - ( stud_l - stud_eng ) ) + rail_t ) - ( ( pod_h - outer_t - rvn_head - ( stud_l - stud_eng ) ) )"
equation "d10675 = dr_acc_face_y"
equation "d10677 = fr_wsh_d + 2 * fr_scr_clr"
equation "d10678 = abs(b08_x1)"
equation "d10679 = abs(b08_z)"
equation "d10680 = abs(( dr_acc_face_y + dp_t ) - ( dr_acc_face_y ))"
equation "d10682 = dr_acc_face_y"
equation "d10684 = fr_wsh_d + 2 * fr_scr_clr"
equation "d10685 = abs(b08_x2)"
equation "d10686 = abs(b08_z)"
equation "d10687 = abs(( dr_acc_face_y + dp_t ) - ( dr_acc_face_y ))"
equation "d10689 = dr_acc_face_y"
equation "d10691 = fr_wsh_d + 2 * fr_scr_clr"
equation "d10692 = abs(b08_x3)"
equation "d10693 = abs(b08_z)"
equation "d10694 = abs(( dr_acc_face_y + dp_t ) - ( dr_acc_face_y ))"
equation "d10696 = sb_z0 + lin_t - blk_t"
equation "d10698 = fan_bore"
equation "d10699 = abs(( sb_x0 + fbox_t ) + ( sb_w - 2 * fbox_t ) * 1 / 4)"
equation "d10700 = abs(( -pod_d / 2 ) + sb_yf + sb_d / 2)"
equation "d10701 = ( sb_z0 + lin_t ) - ( sb_z0 + lin_t - blk_t )"
equation "d10703 = sb_z0 + lin_t - blk_t"
equation "d10705 = fan_hole"
equation "d10706 = abs(( sb_x0 + fbox_t ) + ( sb_w - 2 * fbox_t ) * 1 / 4 - fan_hp / 2)"
equation "d10707 = abs(( -pod_d / 2 ) + sb_yf + sb_d / 2 - fan_hp / 2)"
equation "d10708 = ( sb_z0 + lin_t ) - ( sb_z0 + lin_t - blk_t )"
equation "d10710 = sb_z0 + lin_t - blk_t"
equation "d10712 = fan_hole"
equation "d10713 = abs(( sb_x0 + fbox_t ) + ( sb_w - 2 * fbox_t ) * 1 / 4 - fan_hp / 2)"
equation "d10714 = abs(( -pod_d / 2 ) + sb_yf + sb_d / 2 + fan_hp / 2)"
equation "d10715 = ( sb_z0 + lin_t ) - ( sb_z0 + lin_t - blk_t )"
equation "d10717 = sb_z0 + lin_t - blk_t"
equation "d10719 = fan_hole"
equation "d10720 = abs(( sb_x0 + fbox_t ) + ( sb_w - 2 * fbox_t ) * 1 / 4 + fan_hp / 2)"
equation "d10721 = abs(( -pod_d / 2 ) + sb_yf + sb_d / 2 - fan_hp / 2)"
equation "d10722 = ( sb_z0 + lin_t ) - ( sb_z0 + lin_t - blk_t )"
equation "d10724 = sb_z0 + lin_t - blk_t"
equation "d10726 = fan_hole"
equation "d10727 = abs(( sb_x0 + fbox_t ) + ( sb_w - 2 * fbox_t ) * 1 / 4 + fan_hp / 2)"
equation "d10728 = abs(( -pod_d / 2 ) + sb_yf + sb_d / 2 + fan_hp / 2)"
equation "d10729 = ( sb_z0 + lin_t ) - ( sb_z0 + lin_t - blk_t )"
equation "d10731 = sb_z0 + lin_t - blk_t"
equation "d10733 = fan_bore"
equation "d10734 = abs(( sb_x0 + fbox_t ) + ( sb_w - 2 * fbox_t ) * 3 / 4)"
equation "d10735 = abs(( -pod_d / 2 ) + sb_yf + sb_d / 2)"
equation "d10736 = ( sb_z0 + lin_t ) - ( sb_z0 + lin_t - blk_t )"
equation "d10738 = sb_z0 + lin_t - blk_t"
equation "d10740 = fan_hole"
equation "d10741 = abs(( sb_x0 + fbox_t ) + ( sb_w - 2 * fbox_t ) * 3 / 4 - fan_hp / 2)"
equation "d10742 = abs(( -pod_d / 2 ) + sb_yf + sb_d / 2 - fan_hp / 2)"
equation "d10743 = ( sb_z0 + lin_t ) - ( sb_z0 + lin_t - blk_t )"
equation "d10745 = sb_z0 + lin_t - blk_t"
equation "d10747 = fan_hole"
equation "d10748 = abs(( sb_x0 + fbox_t ) + ( sb_w - 2 * fbox_t ) * 3 / 4 - fan_hp / 2)"
equation "d10749 = abs(( -pod_d / 2 ) + sb_yf + sb_d / 2 + fan_hp / 2)"
equation "d10750 = ( sb_z0 + lin_t ) - ( sb_z0 + lin_t - blk_t )"
equation "d10752 = sb_z0 + lin_t - blk_t"
equation "d10754 = fan_hole"
equation "d10755 = abs(( sb_x0 + fbox_t ) + ( sb_w - 2 * fbox_t ) * 3 / 4 + fan_hp / 2)"
equation "d10756 = abs(( -pod_d / 2 ) + sb_yf + sb_d / 2 - fan_hp / 2)"
equation "d10757 = ( sb_z0 + lin_t ) - ( sb_z0 + lin_t - blk_t )"
equation "d10759 = sb_z0 + lin_t - blk_t"
equation "d10761 = fan_hole"
equation "d10762 = abs(( sb_x0 + fbox_t ) + ( sb_w - 2 * fbox_t ) * 3 / 4 + fan_hp / 2)"
equation "d10763 = abs(( -pod_d / 2 ) + sb_yf + sb_d / 2 + fan_hp / 2)"
equation "d10764 = ( sb_z0 + lin_t ) - ( sb_z0 + lin_t - blk_t )"
equation "d10766 = dt_zb + face_t + sof_fill_t + cart_w - blk_t - fan_t + fan_t"
equation "d10768 = fan_bore"
equation "d10769 = abs(( ( pod_w / 2 - stack_t - col_gap ) - fb_w ) + ( fb_w - fbox_t ) * 1 / 4)"
equation "d10770 = abs(dr_acc_face_y + clr + cart_d / 2)"
equation "d10771 = ( dt_zb + face_t + sof_fill_t + cart_w - blk_t - fan_t + fan_t + blk_t ) - ( dt_zb + face_t + sof_fill_t + cart_w - blk_t - fan_t + fan_t )"
equation "d10773 = dt_zb + face_t + sof_fill_t + cart_w - blk_t - fan_t + fan_t"